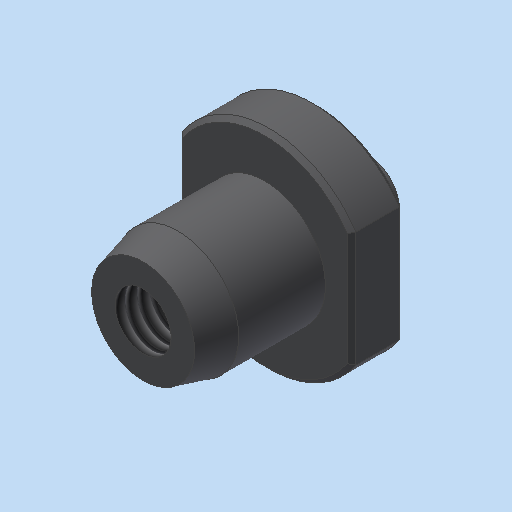
# Autodesk Inventor part: MM0948AN160_G01_113
Saved by Autodesk Inventor 2023.3 (Build 273359000, 359)
## iProperties
Created: 2023-03-23
Part Number: MM0948AN160_G01_113
Document SubType Name: Modeling
Designer: brt9bw
Density: 7.85 g/cm^3
Material: 1.2379 X155CrVMo12-1
Description: =<RBPARTNOTITLE2>
Mass: 4.16852 g
Surface Area: 5.6063 cm^2
Volume: 0.531021 cm^3
Appearance: Stahl - rostfrei AnP
RBPARTNOTITLE1: Teachpin
RBPARTMADEOF: Rd. 12 x 13 (FM)
RBPARTNOTITLE2: Teachstift
RBPARTNO: SIEHE MNR
RBMATNO: =<Part Number>
RBMATERIAL: =<Material>
RBGBDIM_01: 0,000 mm
RBGBDIM_04: 0,000 mm
RBGBDIM_03: 0,000 mm
RBGBDIM_02: 0,000 mm
RBDRAWINGMISSINGSPEC: --
AnP_Kategorie: 1
RBSURFACE: --
AnP_Material: =<Material>
RBSURFACE2: --
AnP_Kommentar_aktuell: =<Comments>
AnP_Material_aktuell: =<Material>
MaxAbmaße: 12 x 13 x 10 (FM)
Author: FH/Wi
Keywords: =<RBPARTMADEOF>
Comments: =<RBSURFACE2>
Revision Number: 01
Autodesk Inventor part; units mm, degrees
ref_plane "YZ Plane" through (0, 0, 0) normal (1, 0, 0) x (0, 1, 0)
ref_plane "XZ Plane" through (0, 0, 0) normal (0, 1, 0) x (-1, 0, 0)
ref_plane "XY Plane" through (0, 0, 0) normal (0, 0, 1) x (1, 0, 0)
sketch "Skizze1" plane through (0, 0, 0) normal (0, 0, 1) x (1, 0, 0)
  line L0 (-1.2, 0) -> (7.2, 0) projected
  line L1 (0, -9.6) -> (0, 8.6) projected
  line L2 (0, -7) -> (3.5, -7)
  line L3 (3.5, -7) -> (3.5, 0)
  line L4 (6, 0) -> (6, 3)
  line L5 (6, 3) -> (1.75, 3)
  line L6 (1.75, 3) -> (1.75, 6)
  line L7 (1.75, 6) -> (0, 6)
  point P0 (0, 0)
  dimension "d0" = 7
  dimension "d1" = 12
  dimension "d2" = 3.5
  dimension "d3" = 3
  dimension "d4" = 6
  dimension "d5" = 7
  constraints: 12 end point, 4 point on line, 3 perpendicular, 2 parallel
  measures "d0" diameter of L3 L1
  measures "d1" diameter of L4 L1
  measures "d2" diameter of L6 L1
  measures "d3" distance between parallel lines of L5 L0
  measures "d4" distance between parallel lines of L7 L0
  measures "d5" distance of L2.end L3.end
revolve "Umdrehung1" add sketch "Skizze1" angle 360 about axis through (0, -10, 0) along (0, 1, 0)
chamfer "Fase1" distance 2 angle 15 1 edges at (-3.5, -7, 0) measured on face at (-3.5, -6.5, 0)
fillet "Rundung1" radius 1 1 edges at (-1.75, 3, 0)
sketch "Skizze2" plane through (0, 0, 0) normal (0, -1, 0) x (1, 0, 0)
  line L0 (0, -8.4) -> (0, 8.4) projected
  line L1 (-8.4, 0) -> (8.4, 0) projected
  line L2 (-5, 6) -> (5, 6)
  line L3 (5, 3.3166) -> (5, -3.3166)
  line L4 (5, -6) -> (-5, -6)
  line L5 (-5, -3.3166) -> (-5, 3.3166)
  circle A0 centre (0, 0) radius 3.5 projected
  circle A1 centre (0, 0) radius 6 projected
  circle A2 centre (0, 0) radius 6 projected
  dimension "d11" = 10
  constraints: 8 end point, 4 point on circle, 2 parallel, 2 tangent, 1 horizontal, 1 perpendicular
  measures "d11" distance between parallel lines of L3 L5
extrude "Extrusion1" cut sketch "Skizze2" against normal up to surface (3 mm away) contours A1 L1 L5 | L3 L1 A1 | L1 A1 L5 | L3 A1 L1
sketch "Skizze3" plane through (0, -7, 0) normal (0, -1, 0) x (1, 0, 0)
  line L0 (-8.4, 0) -> (8.4, 0) projected
  line L1 (0, -8.4) -> (0, 8.4) projected
  point P0 (0, 0)
  point P1 (0, 0)
  constraints: 1 coincident
hole "Bohrung1" at (0, -7, 0) direction (0, 1, 0) diameter 3.242 depth 8 tip angle 118 thread size "M4x0.7" class "6H" standard "ISO Metric profile"
chamfer "Fase2" distance 0.25 angle 45 8 edges at (-5, 3, 0) (0, 3, -6) (5, 3, 0) (0, 3, 6) (0, 0, 6) (-5, 0, 0) (0, 0, -6) (5, 0, 0)
equation "\"RBGBDIM_01\" = 0"
equation "\"RBGBDIM_02\" = 0"
equation "\"RBGBDIM_03\" = 0"
equation "\"RBGBDIM_04\" = 0"
